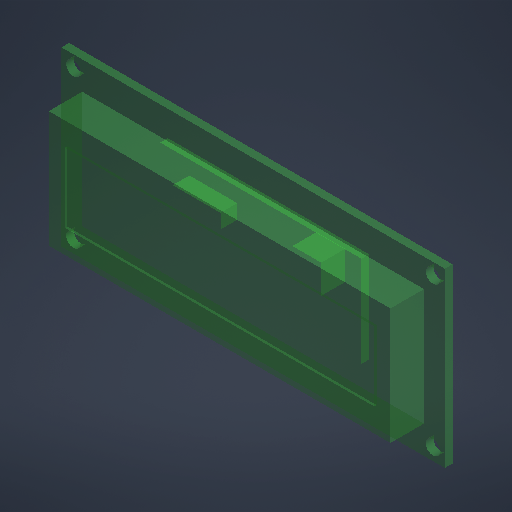
# Autodesk Inventor part: LCD1602_I2C_Module
Saved by Autodesk Inventor 2027.1 (Build 311270010, 270A)
## iProperties
Part Number: LCD1602_I2C_Module
Material: Generic
Document SubType Name: Modeling
Designer: austin
Appearance: Green
Author: austin
Autodesk Inventor part; units mm, degrees
sketch "Sketch1" plane through (0, 0, 0) normal (0, 0, 1) x (1, 0, 0)
  line L0 (-40, -18) -> (40, -18)
  line L1 (40, -18) -> (40, 18)
  line L2 (40, 18) -> (-40, 18)
  line L3 (-40, 18) -> (-40, -18)
  constraints: 8 end point, 2 parallel, 1 horizontal, 1 perpendicular
extrude "Extrusion1" add sketch "Sketch1" along normal blind 1.6
sketch "Sketch2" plane through (0, 0, 0) normal (0, 0, 1) x (1, 0, 0)
  circle A0 centre (-37.5, -15.5) radius 1.5
  circle A1 centre (37.5, -15.5) radius 1.5
  circle A2 centre (-37.5, 15.5) radius 1.5
  circle A3 centre (37.5, 15.5) radius 1.5
  constraints: 4 centre point
extrude "Extrusion2" cut sketch "Sketch2" along normal blind 2
ref_plane "Work Plane1" through (0, 0, 1.6) normal (0, 0, 1) x (1, 0, 0)
sketch "Sketch3" plane through (0, 0, 1.6) normal (0, 0, 1) x (1, 0, 0)
  line L0 (-35.65, -12.15) -> (35.65, -12.15)
  line L1 (35.65, -12.15) -> (35.65, 12.15)
  line L2 (35.65, 12.15) -> (-35.65, 12.15)
  line L3 (-35.65, 12.15) -> (-35.65, -12.15)
  constraints: 8 end point, 2 parallel, 1 horizontal, 1 perpendicular
extrude "Extrusion3" add sketch "Sketch3" along normal blind 7
ref_plane "Work Plane2" through (0, 0, 8.6) normal (0, 0, 1) x (1, 0, 0)
sketch "Sketch4" plane through (0, 0, 8.6) normal (0, 0, 1) x (1, 0, 0)
  line L0 (-32.25, -7.25) -> (32.25, -7.25)
  line L1 (32.25, -7.25) -> (32.25, 7.25)
  line L2 (32.25, 7.25) -> (-32.25, 7.25)
  line L3 (-32.25, 7.25) -> (-32.25, -7.25)
  constraints: 8 end point, 2 parallel, 1 horizontal, 1 perpendicular
extrude "Extrusion4" cut sketch "Sketch4" against normal blind 2.5
ref_plane "Work Plane3" through (0, 0, 6.1) normal (0, 0, 1) x (1, 0, 0)
sketch "Sketch5" plane through (0, 0, 6.1) normal (0, 0, 1) x (1, 0, 0)
  line L0 (-32.25, -7.25) -> (32.25, -7.25)
  line L1 (32.25, -7.25) -> (32.25, 7.25)
  line L2 (32.25, 7.25) -> (-32.25, 7.25)
  line L3 (-32.25, 7.25) -> (-32.25, -7.25)
  constraints: 8 end point, 2 parallel, 1 horizontal, 1 perpendicular
extrude "Extrusion5" add sketch "Sketch5" along normal blind 2
sketch "Sketch6" plane through (0, 0, 0) normal (0, 0, 1) x (1, 0, 0)
  line L0 (-21, -9.5) -> (21, -9.5)
  line L1 (21, -9.5) -> (21, 9.5)
  line L2 (21, 9.5) -> (-21, 9.5)
  line L3 (-21, 9.5) -> (-21, -9.5)
  constraints: 8 end point, 2 parallel, 1 horizontal, 1 perpendicular
extrude "Extrusion6" add sketch "Sketch6" against normal blind 1.6
ref_plane "Work Plane4" through (0, 0, -1.6) normal (0, 0, 1) x (1, 0, 0)
sketch "Sketch7" plane through (0, 0, -1.6) normal (0, 0, 1) x (1, 0, 0)
  line L0 (5, -3) -> (11, -3)
  line L1 (11, -3) -> (11, 3)
  line L2 (11, 3) -> (5, 3)
  line L3 (5, 3) -> (5, -3)
  constraints: 8 end point, 2 parallel, 1 horizontal, 1 perpendicular
extrude "Extrusion7" add sketch "Sketch7" against normal blind 5
sketch "Sketch8" plane through (0, 0, -1.6) normal (0, 0, 1) x (1, 0, 0)
  line L0 (-20, -1.5) -> (-10, -1.5)
  line L1 (-10, -1.5) -> (-10, 1.5)
  line L2 (-10, 1.5) -> (-20, 1.5)
  line L3 (-20, 1.5) -> (-20, -1.5)
  constraints: 8 end point, 2 parallel, 1 horizontal, 1 perpendicular
extrude "Extrusion8" add sketch "Sketch8" against normal blind 3.5
body "Solid1"
